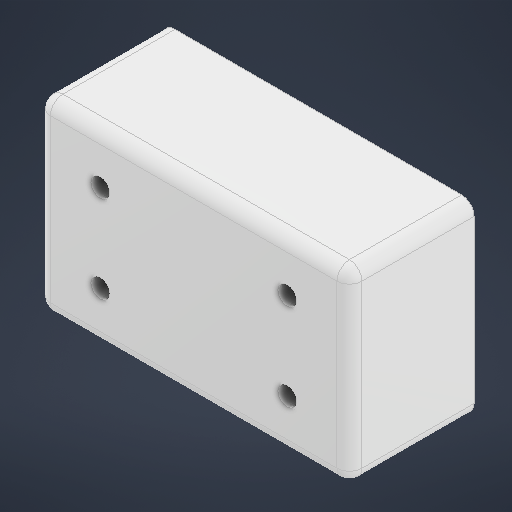
# Autodesk Inventor part: Part1
Saved by Autodesk Inventor 2026.4 (Build 304435000, 435)
## iProperties
Created: 2026-11-06
Part Number: Part1
Material: PC/ABS Plastic
Document SubType Name: Modeling
Designer: s09nuxfu
Density: 1.1 g/cm^3
Appearance: Smooth - White
Author: s09nuxfu
Autodesk Inventor part; units mm, degrees
ref_plane "YZ Plane" through (0, 0, 0) normal (1, 0, 0) x (0, 1, 0)
ref_plane "XZ Plane" through (0, 0, 0) normal (0, 1, 0) x (-1, 0, 0)
ref_plane "XY Plane" through (0, 0, 0) normal (0, 0, 1) x (1, 0, 0)
sketch "Sketch2" plane through (0, 0, 0) normal (0, 0, 1) x (1, 0, 0)
  line L0 (0, 0) -> (50, 0)
  line L1 (50, 0) -> (50, 30)
  line L2 (50, 30) -> (0, 30)
  line L3 (0, 30) -> (0, 0)
  dimension "d2" = 50
  dimension "d3" = 30
  constraints: 8 end point, 2 parallel, 1 horizontal, 1 perpendicular
  measures "d2" distance of L1.end L2.end
  measures "d3" distance of L0.end L1.end
extrude "Extrusion2" add sketch "Sketch2" along normal blind 20
sketch "Sketch3" plane through (0, 0, 20) normal (0, 0, 1) x (1, 0, 0)
  line L0 (0, 30) -> (0, 0) projected
  line L1 (50, 30) -> (0, 30) projected
  point P0 (10, 22)
  dimension "d6" = 10
  dimension "d7" = 8
  measures "d6" distance from line of L0 point (10, 22)
  measures "d7" distance from line of L1 point (10, 22)
hole "Hole1" at (10, 22, 20) direction (0, 0, -1) diameter 3 end through all
pattern_linear "Rectangular Pattern1" count 2 spacing 30 along (1, 0, 0) count 2 spacing 14 along (0, -1, 0) of "Hole1"
fillet "Fillet1" radius 2 8 edges at (0, 15, 20) (0, 30, 10) (25, 30, 20) (50, 30, 10) (50, 15, 20) (25, 0, 20) (50, 0, 10) (0, 0, 10)
shell "Shell1" thickness 1 removed faces 1 at (29.5325, 12.844, 0)
body "Solid2"
